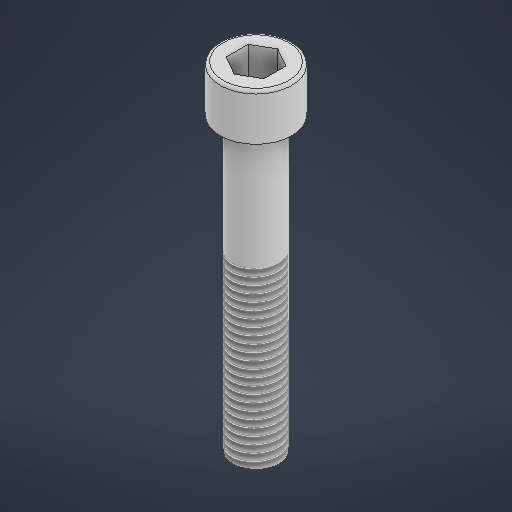
# Autodesk Inventor part: CV_Flange_Bolt_V1
Saved by Autodesk Inventor 2027.1 (Build 311270010, 270A)
## iProperties
Created: 2026-11-23
Part Number: CV_Flange_Bolt_V1
Material: Generic
Document SubType Name: Modeling
Designer: share
Density: 1 g/cm^3
Appearance: Default
Author: share
Autodesk Inventor part; units mm, degrees
ref_plane "YZ Plane" through (0, 0, 0) normal (1, 0, 0) x (0, 1, 0)
ref_plane "XZ Plane" through (0, 0, 0) normal (0, 1, 0) x (-1, 0, 0)
ref_plane "XY Plane" through (0, 0, 0) normal (0, 0, 1) x (1, 0, 0)
sketch "Sketch1" plane through (0, 0, 0) normal (1, 0, 0) x (0, 1, 0)
  line L0 (0, 1.23) -> (0, -7.38) construction
  line L1 (-40.6, 0) -> (40.6, 0) construction
  line L2 (-29, 0) -> (29, 0)
  line L3 (29, 0) -> (29, -6.15)
  line L4 (29, -6.15) -> (21, -6.15)
  line L5 (21, -6.15) -> (21, -4)
  line L6 (21, -4) -> (-29, -4)
  line L7 (-29, -4) -> (-29, 0)
  dimension "d6" = 58
  dimension "d7" = 8
  dimension "d8" = 4
  dimension "d9" = 6.15
  constraints: 12 end point, 4 perpendicular, 2 point on line, 1 vertical, 1 other
  measures "d6" distance between parallel lines of L7 L3
  measures "d7" distance between parallel lines of L5 L3
  measures "d8" distance between parallel lines of L6 L1
  measures "d9" distance between parallel lines of L4 L1
revolve "Revolution1" add sketch "Sketch1" angle 360 about axis through (0, 0, 0) along (0, 1, 0)
sketch "Sketch2" plane through (0, 29, 0) normal (0, 1, 0) x (1, 0, 0)
  line L0 (0, 8.61) -> (0, -8.61) construction
  line L1 (8.61, 0) -> (-8.61, 0) construction
  line L2 (0, -3.7528) -> (-3.25, -1.8764)
  line L3 (-3.25, -1.8764) -> (-3.25, 1.8764)
  line L4 (-3.25, 1.8764) -> (0, 3.7528)
  line L5 (0, 3.7528) -> (3.25, 1.8764)
  line L6 (3.25, 1.8764) -> (3.25, -1.8764)
  line L7 (3.25, -1.8764) -> (0, -3.7528)
  point P0 (0, 0)
  point P1 (0, 0)
  dimension "d11" = 6.5
  constraints: 12 end point, 1 coincident, 1 point on line, 13 other
  measures "d11" distance between parallel lines of L3 L6
extrude "Extrusion1" cut sketch "Sketch2" against normal blind 5
thread "Thread1" size "M8x1.25" class "6g" standard "ANSI Metric M Profile" length 30
fillet "Fillet1" radius 0.5 1 edges at (0, 29, 6.15)
body "Solid1"
